Autodesk Fusion 360 part; units mm, degrees
(part 3 of 3)
  point P107 (-11.4886, -1.5872)
  point P108 (-11.1848, -1.9739)
  point P109 (-10.758, -2.2916)
  point P110 (-10.4351, -2.6467)
  point P111 (-10.3192, -3.1125)
  point P112 (-10.2922, -3.6438)
  point P113 (-10.1395, -4.1113)
  point P114 (-9.766, -4.4314)
  point P115 (-9.2855, -4.6596)
  point P116 (-8.8994, -4.9449)
  point P117 (-8.6949, -5.3792)
  point P118 (-8.5648, -5.895)
  point P119 (-8.3238, -6.3238)
  point P120 (-7.895, -6.5648)
  point P121 (-7.3792, -6.6949)
  point P122 (-6.9449, -6.8994)
  point P123 (-6.6596, -7.2855)
  point P124 (-6.4314, -7.766)
  point P125 (-6.1113, -8.1395)
  point P126 (-5.6438, -8.2922)
  point P127 (-5.1125, -8.3192)
  point P128 (-4.6467, -8.4351)
  point P129 (-4.2916, -8.758)
  point P130 (-3.9739, -9.1848)
  point P131 (-3.5872, -9.4886)
  point P132 (-3.0988, -9.5472)
  point P133 (-2.5725, -9.4701)
  point P134 (-2.093, -9.4929)
  point P135 (-1.6817, -9.7403)
  point P136 (-1.2869, -10.0969)
  point P137 (-0.8483, -10.3195)
  point P138 (-0.3579, -10.2817)
  point P139 (0.1433, -10.1033)
  point P140 (0.618, -10.0321)
  point P141 (1.0696, -10.1945)
  point P142 (1.5264, -10.4672)
  point P143 (2, -10.6)
  point P144 (2.4736, -10.4672)
  point P145 (2.9304, -10.1945)
  point P146 (3.382, -10.0321)
  point P147 (3.8567, -10.1033)
  point P148 (4.3579, -10.2817)
  point P149 (4.8483, -10.3195)
  point P150 (5.2869, -10.0969)
  point P151 (5.6817, -9.7403)
  point P152 (6.093, -9.4929)
  point P153 (6.5725, -9.4701)
  point P154 (7.0988, -9.5472)
  point P155 (7.5872, -9.4886)
  point P156 (7.9739, -9.1848)
  point P157 (8.2916, -8.758)
  point P158 (8.6467, -8.4351)
  point P159 (9.1125, -8.3192)
  point P160 (9.6438, -8.2922)
  point P161 (10.1113, -8.1395)
  point P162 (10.4314, -7.766)
  point P163 (10.6596, -7.2855)
  point P164 (10.9449, -6.8994)
  point P165 (11.3792, -6.6949)
  point P166 (11.895, -6.5648)
  point P167 (12.3238, -6.3238)
  point P168 (12.5648, -5.895)
  point P169 (12.6949, -5.3792)
  point P170 (12.8994, -4.9449)
  point P171 (13.2855, -4.6596)
  point P172 (13.766, -4.4314)
  point P173 (14.1395, -4.1113)
  point P174 (14.2922, -3.6438)
  point P175 (14.3192, -3.1125)
  point P176 (14.4351, -2.6467)
  point P177 (14.758, -2.2916)
  point P178 (15.1848, -1.9739)
  point P179 (15.4886, -1.5872)
  point P180 (15.5472, -1.0988)
  point P181 (15.4701, -0.5725)
  point P182 (15.4929, -0.093)
  point P183 (15.7403, 0.3183)
  point P184 (16.0969, 0.7131)
  point P185 (16.3195, 1.1517)
  point P186 (16.2817, 1.6421)
  point P187 (16.1033, 2.1433)
  point P188 (16.0321, 2.618)
  point P189 (16.1945, 3.0696)
  point P190 (16.4672, 3.5264)
extrude "Extrude1''" add sketch "rim" along normal blind 4.1 separate body makes body 4 in component "wheel"
sketch "bore" plane through (0, 0, 0) normal (0, 0, 1) x (1, 0, 0) in component "wheel"
  circle A0 centre (2, 4) radius 2
  dimension "d2509" = 4
  measures "d2509" diameter of A0
extrude "Extrude2''" cut sketch "bore" along normal blind 2 bodies 4 in component "wheel"
ref_plane "WorkPlane1" through (0, 0, 3.7) normal (0, 0, 1) x (1, 0, 0) in component "wheel"
sketch "hub" plane through (0, 0, 3.7) normal (0, 0, 1) x (1, 0, 0) in component "wheel"
  circle A0 centre (2, 4) radius 6
extrude "Extrude3''" cut sketch "hub" along normal blind 0.5 bodies 4 in component "wheel"
sketch "pin" plane through (0, 0, 3.7) normal (0, 0, 1) x (1, 0, 0) in component "wheel"
  line L0 (2.9584, 4) -> (2.4792, 4.83)
  line L1 (2.4792, 4.83) -> (1.5208, 4.83)
  line L2 (1.5208, 4.83) -> (1.0416, 4)
  line L3 (1.0416, 4) -> (1.5208, 3.17)
  line L4 (1.5208, 3.17) -> (2.4792, 3.17)
  line L5 (2.4792, 3.17) -> (2.9584, 4)
  constraint coincident L0.end L1.start
  constraint coincident L1.end L2.start
  constraint coincident L2.end L3.start
  constraint coincident L3.end L4.start
  constraint coincident L4.end L5.start
  constraint coincident L0.start L5.end
extrude "Extrude4''" add sketch "pin" along normal blind 2.3 separate body makes body 5 in component "wheel"
sketch "pin chamfer" plane through (0, 0, 3.7) normal (0, 0, 1) x (1, 0, 0) in component "wheel"
  circle A0 centre (2, 4) radius 0.9584
extrude "Extrude5''" cut sketch "pin chamfer" along normal blind 2.3 draft -9.343 keep common part bodies 5 in component "wheel"
combine "Combine1'" operation add target body 4 tool bodies 5 in component "wheel"
ref_plane "WorkPlane1" through (0, 0, -60.8) normal (0, 0, 1) x (1, 0, 0) in component "stand-3"
sketch "band" plane through (0, 0, -60.8) normal (0, 0, 1) x (1, 0, 0) in component "stand-3"
  line L0 (1, -125.8) -> (154.125, -125.8)
  line L1 (166.625, -113.3) -> (166.625, 5)
  line L2 (154.125, 17.5) -> (1, 17.5)
  line L3 (-11.5, 5) -> (-11.5, -113.3)
  arc A0 (154.125, -125.8) -> (166.625, -113.3) centre (154.125, -113.3) ccw
  arc A1 (166.625, 5) -> (154.125, 17.5) centre (154.125, 5) ccw
  arc A2 (1, 17.5) -> (-11.5, 5) centre (1, 5) ccw
  arc A3 (-11.5, -113.3) -> (1, -125.8) centre (1, -113.3) ccw
  line L4 (4.5, -109.8) -> (150.625, -109.8)
  line L5 (150.625, -109.8) -> (150.625, 1.5)
  line L6 (150.625, 1.5) -> (4.5, 1.5)
  line L7 (4.5, 1.5) -> (4.5, -109.8)
  constraint coincident L4.end L5.start
  constraint coincident L5.end L6.start
  constraint coincident L6.end L7.start
  constraint coincident L4.start L7.end
extrude "Extrude1'''" add sketch "band" along normal blind 60 separate body makes body 6 in component "stand-3"
sketch "front cut" plane through (0, 0, -60.8) normal (0, 0, 1) x (1, 0, 0) in component "stand-3"
  line L0 (-12.5, -126.8) -> (167.625, -126.8)
  line L1 (167.625, -126.8) -> (167.625, -35.5)
  line L2 (167.625, -35.5) -> (-12.5, -35.5)
  line L3 (-12.5, -35.5) -> (-12.5, -126.8)
  constraint coincident L0.end L1.start
  constraint coincident L1.end L2.start
  constraint coincident L2.end L3.start
  constraint coincident L0.start L3.end
extrude "Extrude2'''" cut sketch "front cut" along normal blind 61 bodies 6 in component "stand-3"
fillet "Fillet1''" radius 2 30 edges at (-3.5, -35.5, -0.8) (4.5, -17, -0.8) (77.5625, 1.5, -0.8) (150.625, -17, -0.8) (158.625, -35.5, -0.8) (166.625, -15.25, -0.8) (162.9638, 13.8388, -0.8) (77.5625, 17.5, -0.8) (-7.8388, 13.8388, -0.8) (-11.5, -15.25, -0.8) (162.9638, 13.8388, -0.8) (77.5625, 17.5, -0.8) (-7.8388, 13.8388, -0.8) (-11.5, -15.25, -0.8) (166.625, -15.25, -0.8) (77.5625, 17.5, -0.8) (-7.8388, 13.8388, -0.8) (-11.5, -15.25, -0.8) (162.9638, 13.8388, -0.8) (166.625, -15.25, -0.8) (-7.8388, 13.8388, -0.8) (-11.5, -15.25, -0.8) (77.5625, 17.5, -0.8) (162.9638, 13.8388, -0.8) (166.625, -15.25, -0.8) (-11.5, -15.25, -0.8) (-7.8388, 13.8388, -0.8) (77.5625, 17.5, -0.8) (162.9638, 13.8388, -0.8) (166.625, -15.25, -0.8) on bodies 6 in component "stand-3"
sketch "desk 3" plane through (0, 0, 0) normal (1, 0, 0) x (0, 0, -1) in component "stand-3"
  line L0 (-11.9895, -400) -> (29.9368, 400)
  line L1 (29.9368, 400) -> (529.9368, 400)
  line L2 (529.9368, 400) -> (488.0105, -400)
  line L3 (488.0105, -400) -> (-11.9895, -400)
  constraint coincident L0.end L1.start
  constraint coincident L1.end L2.start
  constraint coincident L2.end L3.start
  constraint coincident L0.start L3.end
extrude "Extrude3'''" cut sketch "desk 3" along normal mid plane 400 bodies 6 in component "stand-3"
ref_plane "WorkPlane2" through (0, 0, -2.8) normal (0, 0, 1) x (1, 0, 0) in component "stand-3"
sketch "pockets" plane through (0, 0, -2.8) normal (0, 0, 1) x (1, 0, 0) in component "stand-3"
  circle A0 centre (26.5, 9.5) radius 5.05
  circle A1 centre (156.125, 9.5) radius 5.05
  circle A2 centre (-3.5, -20.5) radius 5.05
  dimension "d2546" = 10.1
  dimension "d2547" = 10.1
  dimension "d2548" = 10.1
  measures "d2546" diameter of A0
  measures "d2547" diameter of A1
  measures "d2548" diameter of A2
extrude "Extrude4'''" cut sketch "pockets" along normal blind 2.01 bodies 6 in component "stand-3"
ref_plane "WorkPlane1" through (0, 0, -60.8) normal (0, 0, 1) x (1, 0, 0) in component "stand-6"
sketch "band (2)" plane through (0, 0, -60.8) normal (0, 0, 1) x (1, 0, 0) in component "stand-6"
  line L0 (1, -125.8) -> (154.125, -125.8)
  line L1 (166.625, -113.3) -> (166.625, 5)
  line L2 (154.125, 17.5) -> (1, 17.5)
  line L3 (-11.5, 5) -> (-11.5, -113.3)
  arc A0 (154.125, -125.8) -> (166.625, -113.3) centre (154.125, -113.3) ccw
  arc A1 (166.625, 5) -> (154.125, 17.5) centre (154.125, 5) ccw
  arc A2 (1, 17.5) -> (-11.5, 5) centre (1, 5) ccw
  arc A3 (-11.5, -113.3) -> (1, -125.8) centre (1, -113.3) ccw
  line L4 (4.5, -109.8) -> (150.625, -109.8)
  line L5 (150.625, -109.8) -> (150.625, 1.5)
  line L6 (150.625, 1.5) -> (4.5, 1.5)
  line L7 (4.5, 1.5) -> (4.5, -109.8)
  constraint coincident L4.end L5.start
  constraint coincident L5.end L6.start
  constraint coincident L6.end L7.start
  constraint coincident L4.start L7.end
extrude "Extrude1''''" add sketch "band (2)" along normal blind 60 separate body makes body 7 in component "stand-6"
sketch "front cut (2)" plane through (0, 0, -60.8) normal (0, 0, 1) x (1, 0, 0) in component "stand-6"
  line L0 (-12.5, -126.8) -> (167.625, -126.8)
  line L1 (167.625, -126.8) -> (167.625, -35.5)
  line L2 (167.625, -35.5) -> (-12.5, -35.5)
  line L3 (-12.5, -35.5) -> (-12.5, -126.8)
  constraint coincident L0.end L1.start
  constraint coincident L1.end L2.start
  constraint coincident L2.end L3.start
  constraint coincident L0.start L3.end
extrude "Extrude2''''" cut sketch "front cut (2)" along normal blind 61 bodies 7 in component "stand-6"
fillet "Fillet1'''" radius 2 30 edges at (-3.5, -35.5, -0.8) (4.5, -17, -0.8) (77.5625, 1.5, -0.8) (150.625, -17, -0.8) (158.625, -35.5, -0.8) (166.625, -15.25, -0.8) (162.9638, 13.8388, -0.8) (77.5625, 17.5, -0.8) (-7.8388, 13.8388, -0.8) (-11.5, -15.25, -0.8) (162.9638, 13.8388, -0.8) (77.5625, 17.5, -0.8) (-7.8388, 13.8388, -0.8) (-11.5, -15.25, -0.8) (166.625, -15.25, -0.8) (77.5625, 17.5, -0.8) (-7.8388, 13.8388, -0.8) (-11.5, -15.25, -0.8) (162.9638, 13.8388, -0.8) (166.625, -15.25, -0.8) (-7.8388, 13.8388, -0.8) (-11.5, -15.25, -0.8) (77.5625, 17.5, -0.8) (162.9638, 13.8388, -0.8) (166.625, -15.25, -0.8) (-11.5, -15.25, -0.8) (-7.8388, 13.8388, -0.8) (77.5625, 17.5, -0.8) (162.9638, 13.8388, -0.8) (166.625, -15.25, -0.8) on bodies 7 in component "stand-6"
sketch "desk 6" plane through (0, 0, 0) normal (1, 0, 0) x (0, 0, -1) in component "stand-6"
  line L0 (-26.8602, -400) -> (57.2228, 400)
  line L1 (57.2228, 400) -> (557.2228, 400)
  line L2 (557.2228, 400) -> (473.1398, -400)
  line L3 (473.1398, -400) -> (-26.8602, -400)
  constraint coincident L0.end L1.start
  constraint coincident L1.end L2.start
  constraint coincident L2.end L3.start
  constraint coincident L0.start L3.end
extrude "Extrude3''''" cut sketch "desk 6" along normal mid plane 400 bodies 7 in component "stand-6"
ref_plane "WorkPlane2" through (0, 0, -2.8) normal (0, 0, 1) x (1, 0, 0) in component "stand-6"
sketch "pockets (2)" plane through (0, 0, -2.8) normal (0, 0, 1) x (1, 0, 0) in component "stand-6"
  circle A0 centre (26.5, 9.5) radius 5.05
  circle A1 centre (156.125, 9.5) radius 5.05
  circle A2 centre (-3.5, -20.5) radius 5.05
  dimension "d2563" = 10.1
  dimension "d2564" = 10.1
  dimension "d2565" = 10.1
  measures "d2563" diameter of A0
  measures "d2564" diameter of A1
  measures "d2565" diameter of A2
extrude "Extrude4''''" cut sketch "pockets (2)" along normal blind 2.01 bodies 7 in component "stand-6"
ref_plane "WorkPlane1" through (0, 0, -60.8) normal (0, 0, 1) x (1, 0, 0) in component "stand-9"
sketch "band (3)" plane through (0, 0, -60.8) normal (0, 0, 1) x (1, 0, 0) in component "stand-9"
  line L0 (1, -125.8) -> (154.125, -125.8)
  line L1 (166.625, -113.3) -> (166.625, 5)
  line L2 (154.125, 17.5) -> (1, 17.5)
  line L3 (-11.5, 5) -> (-11.5, -113.3)
  arc A0 (154.125, -125.8) -> (166.625, -113.3) centre (154.125, -113.3) ccw
  arc A1 (166.625, 5) -> (154.125, 17.5) centre (154.125, 5) ccw
  arc A2 (1, 17.5) -> (-11.5, 5) centre (1, 5) ccw
  arc A3 (-11.5, -113.3) -> (1, -125.8) centre (1, -113.3) ccw
  line L4 (4.5, -109.8) -> (150.625, -109.8)
  line L5 (150.625, -109.8) -> (150.625, 1.5)
  line L6 (150.625, 1.5) -> (4.5, 1.5)
  line L7 (4.5, 1.5) -> (4.5, -109.8)
  constraint coincident L4.end L5.start
  constraint coincident L5.end L6.start
  constraint coincident L6.end L7.start
  constraint coincident L4.start L7.end
extrude "Extrude1'''''" add sketch "band (3)" along normal blind 60 separate body makes body 8 in component "stand-9"
sketch "front cut (3)" plane through (0, 0, -60.8) normal (0, 0, 1) x (1, 0, 0) in component "stand-9"
  line L0 (-12.5, -126.8) -> (167.625, -126.8)
  line L1 (167.625, -126.8) -> (167.625, -35.5)
  line L2 (167.625, -35.5) -> (-12.5, -35.5)
  line L3 (-12.5, -35.5) -> (-12.5, -126.8)
  constraint coincident L0.end L1.start
  constraint coincident L1.end L2.start
  constraint coincident L2.end L3.start
  constraint coincident L0.start L3.end
extrude "Extrude2'''''" cut sketch "front cut (3)" along normal blind 61 bodies 8 in component "stand-9"
fillet "Fillet1''''" radius 2 30 edges at (-3.5, -35.5, -0.8) (4.5, -17, -0.8) (77.5625, 1.5, -0.8) (150.625, -17, -0.8) (158.625, -35.5, -0.8) (166.625, -15.25, -0.8) (162.9638, 13.8388, -0.8) (77.5625, 17.5, -0.8) (-7.8388, 13.8388, -0.8) (-11.5, -15.25, -0.8) (162.9638, 13.8388, -0.8) (77.5625, 17.5, -0.8) (-7.8388, 13.8388, -0.8) (-11.5, -15.25, -0.8) (166.625, -15.25, -0.8) (77.5625, 17.5, -0.8) (-7.8388, 13.8388, -0.8) (-11.5, -15.25, -0.8) (162.9638, 13.8388, -0.8) (166.625, -15.25, -0.8) (-7.8388, 13.8388, -0.8) (-11.5, -15.25, -0.8) (77.5625, 17.5, -0.8) (162.9638, 13.8388, -0.8) (166.625, -15.25, -0.8) (-11.5, -15.25, -0.8) (-7.8388, 13.8388, -0.8) (77.5625, 17.5, -0.8) (162.9638, 13.8388, -0.8) (166.625, -15.25, -0.8) on bodies 8 in component "stand-9"
sketch "desk 9" plane through (0, 0, 0) normal (1, 0, 0) x (0, 0, -1) in component "stand-9"
  line L0 (-41.8959, -400) -> (84.8113, 400)
  line L1 (84.8113, 400) -> (584.8113, 400)
  line L2 (584.8113, 400) -> (458.1041, -400)
  line L3 (458.1041, -400) -> (-41.8959, -400)
  constraint coincident L0.end L1.start
  constraint coincident L1.end L2.start
  constraint coincident L2.end L3.start
  constraint coincident L0.start L3.end
extrude "Extrude3'''''" cut sketch "desk 9" along normal mid plane 400 bodies 8 in component "stand-9"
ref_plane "WorkPlane2" through (0, 0, -2.8) normal (0, 0, 1) x (1, 0, 0) in component "stand-9"
sketch "pockets (3)" plane through (0, 0, -2.8) normal (0, 0, 1) x (1, 0, 0) in component "stand-9"
  circle A0 centre (26.5, 9.5) radius 5.05
  circle A1 centre (156.125, 9.5) radius 5.05
  circle A2 centre (-3.5, -20.5) radius 5.05
  dimension "d2580" = 10.1
  dimension "d2581" = 10.1
  dimension "d2582" = 10.1
  measures "d2580" diameter of A0
  measures "d2581" diameter of A1
  measures "d2582" diameter of A2
extrude "Extrude4'''''" cut sketch "pockets (3)" along normal blind 2.01 bodies 8 in component "stand-9"
ref_plane "WorkPlane13" through (0, 0, 8.1) normal (0, 0, 1) x (1, 0, 0) in component "tray"
sketch "cap lug slot" plane through (0, 0, 8.1) normal (0, 0, 1) x (1, 0, 0) in component "tray"
  line L0 (-8.8845, -5.9589) -> (-10.037, -7.2086)
  line L1 (-10.037, -7.2086) -> (-8.1992, -8.9035)
  line L2 (-8.1992, -8.9035) -> (-7.0467, -7.6538)
  line L3 (-7.0467, -7.6538) -> (-8.8845, -5.9589)
  constraint coincident L0.end L1.start
  constraint coincident L1.end L2.start
  constraint coincident L2.end L3.start
  constraint coincident L0.start L3.end
extrude "Extrude20" [suppressed] in component "tray"
ref_plane "WorkPlane14" through (0, 0, 6.8) normal (0, 0, 1) x (1, 0, 0) in component "tray"
sketch "cap seat" plane through (0, 0, 6.8) normal (0, 0, 1) x (1, 0, 0) in component "tray"
  line L0 (-12.5, -10.17) -> (16.17, -10.17)
  line L1 (16.17, -10.17) -> (16.17, 18.5)
  line L2 (16.17, 18.5) -> (-12.5, 18.5)
  line L3 (-12.5, 18.5) -> (-12.5, -10.17)
  constraint coincident L0.end L1.start
  constraint coincident L1.end L2.start
  constraint coincident L2.end L3.start
  constraint coincident L0.start L3.end
extrude "Extrude21" [suppressed] in component "tray"
sketch "cap seat cavity" plane through (0, 0, 6.8) normal (0, 0, 1) x (1, 0, 0) in component "tray"
  line L0 (1, -117.8) -> (154.125, -117.8)
  line L1 (158.625, -113.3) -> (158.625, 5)
  line L2 (154.125, 9.5) -> (1, 9.5)
  line L3 (-3.5, 5) -> (-3.5, -113.3)
  arc A0 (154.125, -117.8) -> (158.625, -113.3) centre (154.125, -113.3) ccw
  arc A1 (158.625, 5) -> (154.125, 9.5) centre (154.125, 5) ccw
  arc A2 (1, 9.5) -> (-3.5, 5) centre (1, 5) ccw
  arc A3 (-3.5, -113.3) -> (1, -117.8) centre (1, -113.3) ccw
extrude "Extrude22" [suppressed] in component "tray"
combine "Combine1''" [suppressed] in component "tray"
ref_plane "WorkPlane15" through (0, 0, 7.6) normal (0, 0, 1) x (1, 0, 0) in component "tray"
sketch "cap lug slots" plane through (0, 0, 7.6) normal (0, 0, 1) x (1, 0, 0) in component "tray"
  line L0 (14.9035, 14.1992) -> (13.2086, 16.037)
  line L1 (13.2086, 16.037) -> (11.9589, 14.8845)
  line L2 (11.9589, 14.8845) -> (13.6538, 13.0467)
  line L3 (13.6538, 13.0467) -> (14.9035, 14.1992)
  line L4 (-7.0467, -7.6538) -> (-8.8845, -5.9589)
  line L5 (-8.8845, -5.9589) -> (-10.037, -7.2086)
  line L6 (-10.037, -7.2086) -> (-8.1992, -8.9035)
  line L7 (-8.1992, -8.9035) -> (-7.0467, -7.6538)
  constraint coincident L0.end L1.start
  constraint coincident L1.end L2.start
  constraint coincident L2.end L3.start
  constraint coincident L0.start L3.end
  constraint coincident L4.end L5.start
  constraint coincident L5.end L6.start
  constraint coincident L6.end L7.start
  constraint coincident L4.start L7.end
extrude "Extrude23" cut sketch "cap lug slots" along normal blind 3.51 bodies 1 in component "tray"
ref_plane "WorkPlane1" through (0, 0, 6.8) normal (0, 0, 1) x (1, 0, 0) in component "wheel-cap"
sketch "outline (3)" plane through (0, 0, 6.8) normal (0, 0, 1) x (1, 0, 0) in component "wheel-cap"
  line L0 (1, -125.8) -> (154.125, -125.8)
  line L1 (166.625, -113.3) -> (166.625, 5)
  line L2 (154.125, 17.5) -> (1, 17.5)
  line L3 (-11.5, 5) -> (-11.5, -113.3)
  arc A0 (154.125, -125.8) -> (166.625, -113.3) centre (154.125, -113.3) ccw
  arc A1 (166.625, 5) -> (154.125, 17.5) centre (154.125, 5) ccw
  arc A2 (1, 17.5) -> (-11.5, 5) centre (1, 5) ccw
  arc A3 (-11.5, -113.3) -> (1, -125.8) centre (1, -113.3) ccw
extrude "Extrude1''''''" add sketch "outline (3)" along normal blind 7.3 separate body makes body 9 in component "wheel-cap"
fillet "Fillet1'''''" radius 0.6 64 edges at (-7.8388, -122.1388, 14.1) (77.5625, -125.8, 14.1) (162.9638, -122.1388, 14.1) (166.625, -54.15, 14.1) (162.9638, 13.8388, 14.1) (77.5625, 17.5, 14.1) (-7.8388, 13.8388, 14.1) (-11.5, -54.15, 14.1) (77.5625, -125.8, 14.1) (162.9638, -122.1388, 14.1) (166.625, -54.15, 14.1) (162.9638, 13.8388, 14.1) (77.5625, 17.5, 14.1) (-7.8388, 13.8388, 14.1) (-11.5, -54.15, 14.1) (-7.8388, -122.1388, 14.1) (162.9638, -122.1388, 14.1) (166.625, -54.15, 14.1) (162.9638, 13.8388, 14.1) (77.5625, 17.5, 14.1) (-7.8388, 13.8388, 14.1) (-11.5, -54.15, 14.1) (-7.8388, -122.1388, 14.1) (77.5625, -125.8, 14.1) (166.625, -54.15, 14.1) (162.9638, 13.8388, 14.1) (77.5625, 17.5, 14.1) (-7.8388, 13.8388, 14.1) (-11.5, -54.15, 14.1) (-7.8388, -122.1388, 14.1) (77.5625, -125.8, 14.1) (162.9638, -122.1388, 14.1) (162.9638, 13.8388, 14.1) (77.5625, 17.5, 14.1) (-7.8388, 13.8388, 14.1) (-11.5, -54.15, 14.1) (-7.8388, -122.1388, 14.1) (77.5625, -125.8, 14.1) (162.9638, -122.1388, 14.1) (166.625, -54.15, 14.1) (77.5625, 17.5, 14.1) (-7.8388, 13.8388, 14.1) (-11.5, -54.15, 14.1) (-7.8388, -122.1388, 14.1) (77.5625, -125.8, 14.1) (162.9638, -122.1388, 14.1) (166.625, -54.15, 14.1) (162.9638, 13.8388, 14.1) (-7.8388, 13.8388, 14.1) (-11.5, -54.15, 14.1) (-7.8388, -122.1388, 14.1) (77.5625, -125.8, 14.1) (162.9638, -122.1388, 14.1) (166.625, -54.15, 14.1) (162.9638, 13.8388, 14.1) (77.5625, 17.5, 14.1) (-11.5, -54.15, 14.1) (-7.8388, -122.1388, 14.1) (77.5625, -125.8, 14.1) (162.9638, -122.1388, 14.1) (166.625, -54.15, 14.1) (162.9638, 13.8388, 14.1) (77.5625, 17.5, 14.1) (-7.8388, 13.8388, 14.1) on bodies 9 in component "wheel-cap"
sketch "cavity (2)" plane through (0, 0, 6.8) normal (0, 0, 1) x (1, 0, 0) in component "wheel-cap"
  line L0 (1, -117.8) -> (154.125, -117.8)
  line L1 (158.625, -113.3) -> (158.625, 5)
  line L2 (154.125, 9.5) -> (1, 9.5)
  line L3 (-3.5, 5) -> (-3.5, -113.3)
  arc A0 (154.125, -117.8) -> (158.625, -113.3) centre (154.125, -113.3) ccw
  arc A1 (158.625, 5) -> (154.125, 9.5) centre (154.125, 5) ccw
  arc A2 (1, 9.5) -> (-3.5, 5) centre (1, 5) ccw
  arc A3 (-3.5, -113.3) -> (1, -117.8) centre (1, -113.3) ccw
extrude "Extrude2''''''" cut sketch "cavity (2)" along normal blind 7.4 bodies 9 in component "wheel-cap"
sketch "lower tier" plane through (0, 0, 6.8) normal (0, 0, 1) x (1, 0, 0) in component "wheel-cap"
  circle A0 centre (2, 4) radius 15.05
extrude "Extrude3''''''" add sketch "lower tier" along normal blind 4.3 separate body makes body 10 in component "wheel-cap"
ref_plane "WorkPlane2" through (0, 0, 11.1) normal (0, 0, 1) x (1, 0, 0) in component "wheel-cap"
sketch "shoulder" plane through (0, 0, 11.1) normal (0, 0, 1) x (1, 0, 0) in component "wheel-cap"
  circle A0 centre (2, 4) radius 17.05
extrude "Extrude4''''''" add sketch "shoulder" along normal blind 3.01 separate body makes body 11 in component "wheel-cap"
combine "Combine1'''" operation add target body 10 tool bodies 11 in component "wheel-cap"
combine "Combine2" operation intersect target body 9 tool bodies 10 in component "wheel-cap"
ref_plane "WorkPlane3" through (0, 0, 7.75) normal (0, 0, 1) x (1, 0, 0) in component "wheel-cap"
sketch "cap lugs" plane through (0, 0, 7.75) normal (0, 0, 1) x (1, 0, 0) in component "wheel-cap"
  line L0 (14.6915, 14.2077) -> (13.2001, 15.825)
  line L1 (13.2001, 15.825) -> (12.0606, 14.7742)
  line L2 (12.0606, 14.7742) -> (13.5521, 13.157)
  line L3 (13.5521, 13.157) -> (14.6915, 14.2077)
  line L4 (-7.157, -7.5521) -> (-8.7742, -6.0606)
  line L5 (-8.7742, -6.0606) -> (-9.825, -7.2001)
  line L6 (-9.825, -7.2001) -> (-8.2077, -8.6915)
  line L7 (-8.2077, -8.6915) -> (-7.157, -7.5521)
  constraint coincident L0.end L1.start
  constraint coincident L1.end L2.start
  constraint coincident L2.end L3.start
  constraint coincident L0.start L3.end
  constraint coincident L4.end L5.start
  constraint coincident L5.end L6.start
  constraint coincident L6.end L7.start
  constraint coincident L4.start L7.end
extrude "Extrude5'''" add sketch "cap lugs" along normal blind 3.35 bodies 9 in component "wheel-cap"
component "tray" placed x (1, 0, 0) y (0, 1, 0) z (0, 0, 1) at (0, 0, 0)
component "plate" placed x (1, 0, 0) y (0, 1, 0) z (0, 0, 1) at (0, 0, 14.1)
component "wheel" placed x (1, 0, 0) y (0, 1, 0) z (0, 0, 1) at (0, 0, 2.3)
component "stand-3" placed x (1, 0, 0) y (0, 1, 0) z (0, 0, 1) at (0, 0, 0)
component "stand-6" placed x (1, 0, 0) y (0, 1, 0) z (0, 0, 1) at (0, 0, 0)
component "stand-9" placed x (1, 0, 0) y (0, 1, 0) z (0, 0, 1) at (0, 0, 0)
component "wheel-cap" placed x (1, 0, 0) y (0, 1, 0) z (0, 0, 1) at (0, 0, 0)
equation "DRUM_D = 13.0 mm" comment "make_case.py"
equation "DRUM_GAP = 0.4 mm" comment "make_case.py"
equation "DRUM_W = 21.6 mm" comment "make_case.py"
equation "CLEAR = 0.5 mm" comment "make_case.py"
equation "WALL = 8.0 mm" comment "make_case.py"
equation "SCREW_D = 2.2 mm" comment "make_case.py"
equation "PLATE_T = 1.5 mm" comment "make_case.py"
equation "PCB_T = 1.6 mm" comment "make_case.py"
equation "PLATE_GAP = 3.5 mm" comment "make_case.py"
equation "STANDOFF = 7.0 mm" comment "make_case.py"
equation "BOTTOM_T = 3.0 mm" comment "make_case.py"
equation "FRAME_T = 3.0 mm" comment "make_case.py"
equation "N_FRAMES = 4.0" comment "make_case.py"
equation "USB_SHELL_0 = 8.94 mm" comment "make_case.py"
equation "USB_SHELL_1 = 3.26 mm" comment "make_case.py"
equation "PORT_CLR = 0.2 mm" comment "make_case.py"
equation "CHANNEL_CLR = 0.3 mm" comment "make_case.py"
equation "PORT_KEEP = 3.0 mm" comment "make_case.py"
equation "PORT_LIFT = 2.0 mm" comment "make_case.py"
equation "FLOOR = 2.0 mm" comment "make_case.py"
equation "BOSS_D = 4.6 mm" comment "make_case.py"
equation "PILOT_D = 1.6 mm" comment "make_case.py"
equation "INSERT_D = 3.2 mm" comment "make_case.py"
equation "INSERT_DEPTH = 4.0 mm" comment "make_case.py"
equation "SCREW_CB_0 = 4.6 mm" comment "make_case.py"
equation "SCREW_CB_1 = 1.6 mm" comment "make_case.py"
equation "PLATE_BOSS_0 = 5.6 mm" comment "make_case.py"
equation "PLATE_BOSS_1 = 3.0 mm" comment "make_case.py"
equation "BOSS_POCKET_0 = 6.0 mm" comment "make_case.py"
equation "BOSS_POCKET_1 = 3.2 mm" comment "make_case.py"
equation "NUT_TRAP_0 = 4.15 mm" comment "make_case.py"
equation "NUT_TRAP_1 = 1.8 mm" comment "make_case.py"
equation "RESET_D = 3.0 mm" comment "make_case.py"
equation "BUTTON_HOLE = 4.5 mm" comment "make_case.py"
equation "BUTTON_KEEP = 3.6 mm" comment "make_case.py"
equation "CAP_SHOULDER = 2.0 mm" comment "make_case.py"
equation "CAP_LEDGE = 3.0 mm" comment "make_case.py"
equation "CAP_FIT = 0.15 mm" comment "make_case.py"
equation "RIB_T = 2.0 mm" comment "make_case.py"
equation "TRAY_FILLET = 2.0 mm" comment "make_case.py"
equation "TRAY_TOP_FILLET = 0.6 mm" comment "make_case.py"
equation "FOOT_D = 10.0 mm" comment "make_case.py"
equation "FOOT_DEPTH = 1.0 mm" comment "make_case.py"
equation "FOOT_INSET = 8.0 mm" comment "make_case.py"
equation "FOOT_KEEP = 1.0 mm" comment "make_case.py"
equation "FOOT_STEP = 0.5 mm" comment "make_case.py"
equation "FOOT_H = 3.8 mm" comment "make_case.py"
equation "FOOT_PROUD = 2.8 mm" comment "make_case.py"
equation "STAND_ANGLES_0 = 3.0 deg" comment "make_case.py"
equation "STAND_ANGLES_1 = 6.0 deg" comment "make_case.py"
equation "STAND_ANGLES_2 = 9.0 deg" comment "make_case.py"
equation "STAND_W = 16.0 mm" comment "make_case.py"
equation "STAND_POCKET_0 = 10.1 mm" comment "make_case.py"
equation "STAND_POCKET_1 = 2.0 mm" comment "make_case.py"
equation "STAND_PAST = 15.0 mm" comment "make_case.py"
equation "STAND_FILLET = 2.0 mm" comment "make_case.py"
equation "STAND_FLOOR = 1.5 mm" comment "make_case.py"
equation "BED = 220.0 mm" comment "make_case.py"
equation "PLATE_FILLET = 1.0 mm" comment "make_case.py"
equation "SWITCH_CUT = 14.0 mm" comment "make_case.py"
equation "OLED_WINDOW_CLEAR = 0.15 mm" comment "make_case.py"
equation "COVER_T = 2.0 mm" comment "make_case.py"
equation "COVER_FIT = 0.1 mm" comment "make_case.py"
equation "COVER_BORDER = 5.0 mm" comment "make_case.py"
equation "COVER_FRAME = 5.5 mm" comment "make_case.py"
equation "COVER_END = 1.5 mm" comment "make_case.py"
equation "COVER_BELOW = 2.5 mm" comment "make_case.py"
equation "COVER_MARGIN = 3.0 mm" comment "make_case.py"
equation "WALL_POCKET = 0.5 mm" comment "make_case.py"
equation "TAPE_T = 0.5 mm" comment "make_case.py"
equation "OLED_GLASS_TOP = 2.5 mm" comment "make_case.py"
equation "SWITCH_TOP_KEEPOUT = 8.4 mm" comment "make_case.py"
equation "WHEEL_T = 4.1 mm" comment "make_case.py"
equation "WHEEL_GAP = 0.3 mm" comment "make_case.py"
equation "WHEEL_CUT = 0.6 mm" comment "make_case.py"
equation "WHEEL_KNURLS = 32.0" comment "make_case.py"
equation "TOOTH_DEPTH = 0.5 mm" comment "make_case.py"
equation "BORE_D = 4.0 mm" comment "make_case.py"
equation "BORE_DEPTH = 2.0 mm" comment "make_case.py"
equation "POST_D = 3.6 mm" comment "make_case.py"
equation "AXLE_HOLE_D = 3.2 mm" comment "make_case.py"
equation "ENC_W = 5.7 mm" comment "make_case.py"
equation "ENC_TAB_W = 7.6 mm" comment "make_case.py"
equation "ENC_UP = 2.5 mm" comment "make_case.py"
equation "ENC_DOWN = 3.7 mm" comment "make_case.py"
equation "ENC_H = 2.7 mm" comment "make_case.py"
equation "ENC_HEX_AF = 1.72 mm" comment "make_case.py"
equation "ENC_ROTOR_D = 2.2 mm" comment "make_case.py"
equation "HUB_R = 6.0 mm" comment "make_case.py"
equation "HUB_CLEAR = 0.3 mm" comment "make_case.py"
equation "PIN_AF = 1.66 mm" comment "make_case.py"
equation "PIN_ENGAGE = 2.0 mm" comment "make_case.py"
equation "PIN_CHAMFER = 0.25 mm" comment "make_case.py"
equation "STAB_CUT_0 = 7.0 mm" comment "make_case.py"
equation "STAB_CUT_1 = 15.4 mm" comment "make_case.py"
equation "STAB_CUT_2 = 0.5 mm" comment "make_case.py"
equation "STAB_X = 11.938 mm" comment "make_case.py"
equation "EC10_AXIS = 7.0 mm" comment "make_case.py"
equation "EC10_BRACKET_0 = -6.1 mm" comment "make_case.py"
equation "EC10_BRACKET_1 = -4.9 mm" comment "make_case.py"
equation "EC10_BRACKET_2 = 0.0 mm" comment "make_case.py"
equation "EC10_BRACKET_3 = 4.9 mm" comment "make_case.py"
equation "EC10_BRACKET_4 = 2.0 mm" comment "make_case.py"
equation "EC10_BODY_0 = -5.15 mm" comment "make_case.py"
equation "EC10_BODY_1 = -4.9 mm" comment "make_case.py"
equation "EC10_BODY_2 = -0.65 mm" comment "make_case.py"
equation "EC10_BODY_3 = 4.9 mm" comment "make_case.py"
equation "EC10_BODY_4 = 10.6 mm" comment "make_case.py"
equation "EC10_ROTOR_FACE = -1.3 mm" comment "make_case.py"
equation "EC10_HEX_DEPTH = 1.7 mm" comment "make_case.py"
equation "DRUM_GROOVES = 36.0" comment "make_case.py"
equation "DRUM_GROOVE_DEPTH = 0.4 mm" comment "make_case.py"
equation "DRUM_HELIX = 30.0 deg" comment "make_case.py"
equation "DRUM_CHAMFER = 0.5 mm" comment "make_case.py"
equation "DRUM_PIN_ENGAGE = 1.6 mm" comment "make_case.py"
equation "DRUM_ROUND_PIN_0 = 2.0 mm" comment "make_case.py"
equation "DRUM_ROUND_PIN_1 = 2.5 mm" comment "make_case.py"
equation "BLOCK_T = 3.0 mm" comment "make_case.py"
equation "BLOCK_HALF_W = 3.5 mm" comment "make_case.py"
equation "BLOCK_R = 1.0 mm" comment "make_case.py"
equation "BLOCK_TOP = 8.5 mm" comment "make_case.py"
equation "BLOCK_SLOT_R = 1.1 mm" comment "make_case.py"
equation "BLOCK_LIP = 1.8 mm" comment "make_case.py"
equation "BLOCK_PEG_0 = 1.9 mm" comment "make_case.py"
equation "BLOCK_PEG_1 = 1.4 mm" comment "make_case.py"
equation "PLATE_TOP_Z = 5.0 mm" comment "make_case.py"
equation "DRUM_OPENING_0 = -7.1 mm" comment "make_case.py"
equation "DRUM_OPENING_1 = -7.6 mm" comment "make_case.py"
equation "DRUM_OPENING_2 = 26.0 mm" comment "make_case.py"
equation "DRUM_OPENING_3 = 7.6 mm" comment "make_case.py"
equation "DRUM_OPENING_4 = 1.0 mm" comment "make_case.py"
equation "BEZEL_BORDER = 1.5 mm" comment "make_case.py"
equation "BEZEL_R = 2.3 mm" comment "make_case.py"
equation "BEZEL_FIT = 0.1 mm" comment "make_case.py"
equation "BEZEL_LEDGE = 1.0 mm" comment "make_case.py"
equation "BEZEL_LEDGE_T = 0.8 mm" comment "make_case.py"
equation "BEZEL_LEG_HW = 3.0 mm" comment "make_case.py"
equation "BEZEL_WALL = 1.0 mm" comment "make_case.py"
equation "BEZEL_CLEAR = 0.3 mm" comment "make_case.py"
equation "HOOD_IN_R = 0.8 mm" comment "make_case.py"
equation "HOOD_OUT_R = 2.3 mm" comment "make_case.py"
equation "BEZEL_FILLET = 1.2 mm" comment "make_case.py"
equation "BEZEL_FLAT = 0.8 mm" comment "make_case.py"
equation "d2354 = BOSS_D"
equation "d2355 = BOSS_D"
equation "d2356 = BOSS_D"
equation "d2357 = BOSS_D"
equation "d2358 = BOSS_D"
equation "d2359 = BOSS_D"
equation "d2360 = BOSS_D"
equation "d2361 = BOSS_D"
equation "d2362 = STANDOFF"
equation "d2366 = PILOT_D"
equation "d2367 = PILOT_D"
equation "d2368 = PILOT_D"
equation "d2369 = PILOT_D"
equation "d2370 = PILOT_D"
equation "d2371 = PILOT_D"
equation "d2372 = PILOT_D"
equation "d2373 = PILOT_D"
equation "d2376 = SCREW_D"
equation "d2377 = SCREW_D"
equation "d2378 = SCREW_D"
equation "d2379 = SCREW_D"
equation "d2380 = SCREW_D"
equation "d2381 = SCREW_D"
equation "d2382 = SCREW_D"
equation "d2383 = SCREW_D"
equation "d2384 = SCREW_D"
equation "d2385 = SCREW_D"
equation "d2388 = SCREW_CB_0"
equation "d2389 = SCREW_CB_0"
equation "d2390 = SCREW_CB_0"
equation "d2391 = SCREW_CB_0"
equation "d2392 = SCREW_CB_0"
equation "d2393 = SCREW_CB_0"
equation "d2394 = SCREW_CB_0"
equation "d2395 = SCREW_CB_0"
equation "d2396 = SCREW_CB_0"
equation "d2397 = SCREW_CB_0"
equation "d2398 = SCREW_CB_1"
equation "d2402 = BOSS_POCKET_0"
equation "d2403 = BOSS_POCKET_0"
equation "d2404 = BOSS_POCKET_0"
equation "d2405 = BOSS_POCKET_0"
equation "d2406 = BOSS_POCKET_0"
equation "d2407 = BOSS_POCKET_0"
equation "d2408 = BOSS_POCKET_0"
equation "d2409 = BOSS_POCKET_0"
equation "d2410 = BOSS_POCKET_0"
equation "d2411 = BOSS_POCKET_0"
equation "d2450 = POST_D"
equation "d2453 = RESET_D"
equation "d2456 = FOOT_D"
equation "d2457 = FOOT_D"
equation "d2458 = FOOT_D"
equation "d2459 = FOOT_D"
equation "d2460 = FOOT_D"
equation "d2461 = FOOT_DEPTH"
equation "d2463 = PLATE_T"
equation "d2471 = -( RIB_T )"
equation "d2473 = BOSS_D + 2 mm"
equation "d2474 = BOSS_D + 2 mm"
equation "d2475 = BOSS_D + 2 mm"
equation "d2476 = BOSS_D + 2 mm"
equation "d2477 = BOSS_D + 2 mm"
equation "d2478 = BOSS_D + 2 mm"
equation "d2479 = BOSS_D + 2 mm"
equation "d2480 = BOSS_D + 2 mm"
equation "d2483 = PLATE_BOSS_0"
equation "d2484 = PLATE_BOSS_0"
equation "d2485 = PLATE_BOSS_0"
equation "d2486 = PLATE_BOSS_0"
equation "d2487 = PLATE_BOSS_0"
equation "d2488 = PLATE_BOSS_0"
equation "d2489 = PLATE_BOSS_0"
equation "d2490 = PLATE_BOSS_0"
equation "d2491 = PLATE_BOSS_0"
equation "d2492 = PLATE_BOSS_0"
equation "d2493 = -( PLATE_BOSS_1 )"
equation "d2495 = INSERT_D"
equation "d2496 = INSERT_D"
equation "d2497 = INSERT_D"
equation "d2498 = INSERT_D"
equation "d2499 = INSERT_D"
equation "d2500 = INSERT_D"
equation "d2501 = INSERT_D"
equation "d2502 = INSERT_D"
equation "d2503 = INSERT_D"
equation "d2504 = INSERT_D"
equation "d2505 = -( PLATE_BOSS_1 + 0.01 mm )"
equation "d2507 = WHEEL_T"
equation "d2509 = BORE_D"
equation "d2510 = BORE_DEPTH"
equation "d2546 = STAND_POCKET_0"
equation "d2547 = STAND_POCKET_0"
equation "d2548 = STAND_POCKET_0"
equation "d2549 = STAND_POCKET_1 + 0.01 mm"
equation "d2563 = STAND_POCKET_0"
equation "d2564 = STAND_POCKET_0"
equation "d2565 = STAND_POCKET_0"
equation "d2566 = STAND_POCKET_1 + 0.01 mm"
equation "d2580 = STAND_POCKET_0"
equation "d2581 = STAND_POCKET_0"
equation "d2582 = STAND_POCKET_0"
equation "d2583 = STAND_POCKET_1 + 0.01 mm"
equation "CAP_KEY_0 = 2.5 mm" comment "make_case.py"
equation "CAP_KEY_1 = 1.2 mm" comment "make_case.py"
equation "CAP_KEY_2 = 3.5 mm" comment "make_case.py"
equation "CAP_KEY_SHIFT = 4.0 deg" comment "make_case.py"
equation "FUSION_SIMPLIFY = 0.005 mm" comment "make_case.py"
named bodies: "tray", "plate", "wheel", "stand 3", "stand 6", "stand 9", "wheel cap"
